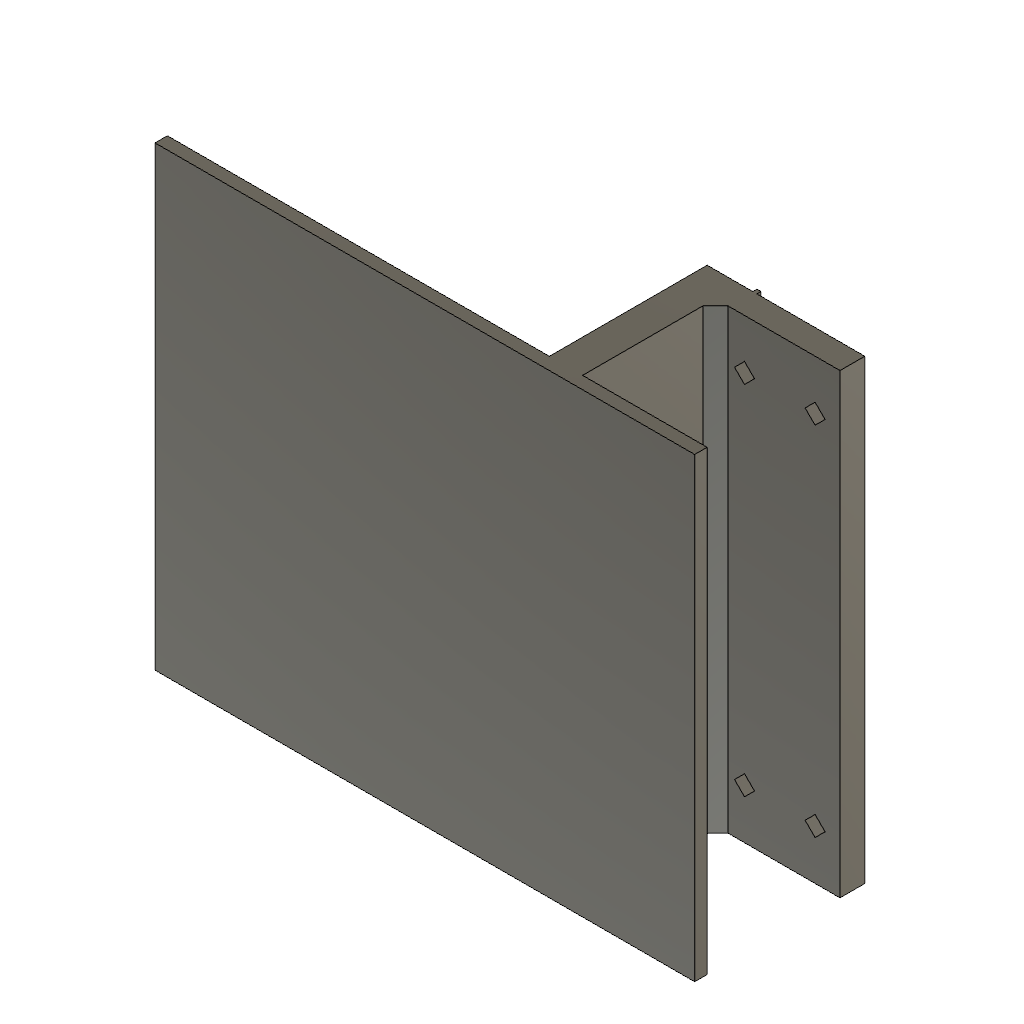
laptop_foot_stand (Autodesk Fusion 360 design; units mm, degrees)
part number: 2026-10-11-03-39-08-205
Autodesk Fusion 360 part; units mm, degrees
sketch "Table deck, back wall, gusset and thin laptop foot sketch" plane through (0, 0, 0) normal (0, 0, 1) x (1, 0, 0)
  line L0 (-104, 0) -> (26, 0)
  line L1 (26, 0) -> (26, 3)
  line L2 (26, 3) -> (-4, 3)
  line L3 (-4, 3) -> (-4, 32)
  line L4 (-4, 32) -> (-1, 35)
  line L5 (-1, 35) -> (26, 35)
  line L6 (26, 35) -> (26, 41)
  line L7 (26, 41) -> (0, 41)
  line L8 (0, 41) -> (0, 42)
  line L9 (0, 42) -> (-1, 42)
  line L10 (-1, 42) -> (-1, 41)
  line L11 (-1, 41) -> (-12, 41)
  line L12 (-12, 41) -> (-12, 3)
  line L13 (-12, 3) -> (-104, 3)
  line L14 (-104, 3) -> (-104, 0)
extrude "Table deck, back wall, gusset and thin laptop foot" add sketch "Table deck, back wall, gusset and thin laptop foot sketch" along normal blind 110
ref_plane "WorkPlane1" through (0, 38, 0) normal (0, 1, 0) x (0, 0, 1)
sketch "M3 diamond clearance (3, -43)" plane through (0, 38, 0) normal (0, 1, 0) x (1, 0, 0)
  line L0 (0.5958, -98) -> (3, -95.5958)
  line L1 (3, -95.5958) -> (5.4042, -98)
  line L2 (5.4042, -98) -> (3, -100.4042)
  line L3 (3, -100.4042) -> (0.5958, -98)
extrude "Support-free M3 bore (3, -43)" cut sketch "M3 diamond clearance (3, -43)" along normal mid plane 6.1
ref_plane "WorkPlane2" through (0, 38, 0) normal (0, 1, 0) x (0, 0, 1)
sketch "M3 diamond clearance (3, 43)" plane through (0, 38, 0) normal (0, 1, 0) x (1, 0, 0)
  line L0 (0.5958, -12) -> (3, -9.5958)
  line L1 (3, -9.5958) -> (5.4042, -12)
  line L2 (5.4042, -12) -> (3, -14.4042)
  line L3 (3, -14.4042) -> (0.5958, -12)
extrude "Support-free M3 bore (3, 43)" cut sketch "M3 diamond clearance (3, 43)" along normal mid plane 6.1
ref_plane "WorkPlane3" through (0, 38, 0) normal (0, 1, 0) x (0, 0, 1)
sketch "M3 diamond clearance (20, -43)" plane through (0, 38, 0) normal (0, 1, 0) x (1, 0, 0)
  line L0 (17.5958, -98) -> (20, -95.5958)
  line L1 (20, -95.5958) -> (22.4042, -98)
  line L2 (22.4042, -98) -> (20, -100.4042)
  line L3 (20, -100.4042) -> (17.5958, -98)
extrude "Support-free M3 bore (20, -43)" cut sketch "M3 diamond clearance (20, -43)" along normal mid plane 6.1
ref_plane "WorkPlane4" through (0, 38, 0) normal (0, 1, 0) x (0, 0, 1)
sketch "M3 diamond clearance (20, 43)" plane through (0, 38, 0) normal (0, 1, 0) x (1, 0, 0)
  line L0 (17.5958, -12) -> (20, -9.5958)
  line L1 (20, -9.5958) -> (22.4042, -12)
  line L2 (22.4042, -12) -> (20, -14.4042)
  line L3 (20, -14.4042) -> (17.5958, -12)
extrude "Support-free M3 bore (20, 43)" cut sketch "M3 diamond clearance (20, 43)" along normal mid plane 6.1
equation "d2 = standWidth"
equation "standWidth = 110 mm" comment "Width along the wing chord"
named bodies: "One native stand solid"
